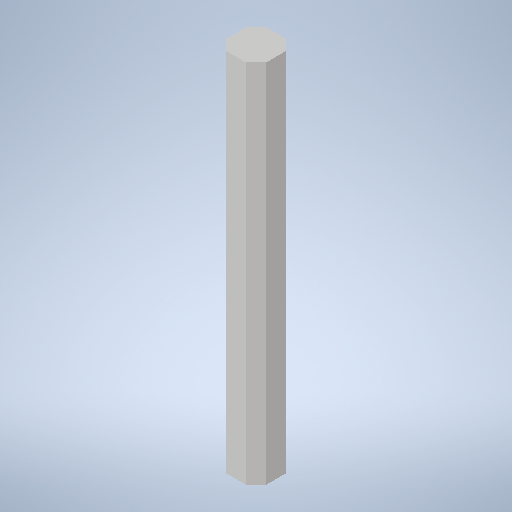
# Autodesk Inventor part: Connector Long
Saved by Autodesk Inventor 2025.2 (Build 292293000, 293)
## iProperties
Created: 2026-07-05
Part Number: Connector Long
Material: Generic
Document SubType Name: Modeling
Designer: crazi
Density: 1 g/cm^3
Appearance: Default
Author: crazi
Autodesk Inventor part; units mm, degrees
ref_plane "YZ Plane" through (0, 0, 0) normal (1, 0, 0) x (0, 1, 0)
ref_plane "XZ Plane" through (0, 0, 0) normal (0, 1, 0) x (-1, 0, 0)
ref_plane "XY Plane" through (0, 0, 0) normal (0, 0, 1) x (1, 0, 0)
sketch "Sketch1" plane through (0, 0, 0) normal (0, 1, 0) x (-1, 0, 0)
  line L0 (0, 0) -> (2, 0)
  line L1 (2, 0) -> (2, -2)
  line L2 (2, -2) -> (0, -2)
  line L3 (0, -2) -> (0, 0)
  dimension "d0" = 2
  dimension "d1" = 2
  constraints: 8 end point, 2 parallel, 1 horizontal, 1 perpendicular
  measures "d0" distance of L1.end L2.end
  measures "d1" distance of L0.end L1.end
extrude "Extrusion1" add sketch "Sketch1" along normal blind 18
chamfer "Chamfer1" distance 0.5 angle 45 4 edges at (0, 9, 0) (0, 9, -2) (-2, 9, -2) (-2, 9, 0)
body "Solid1"
